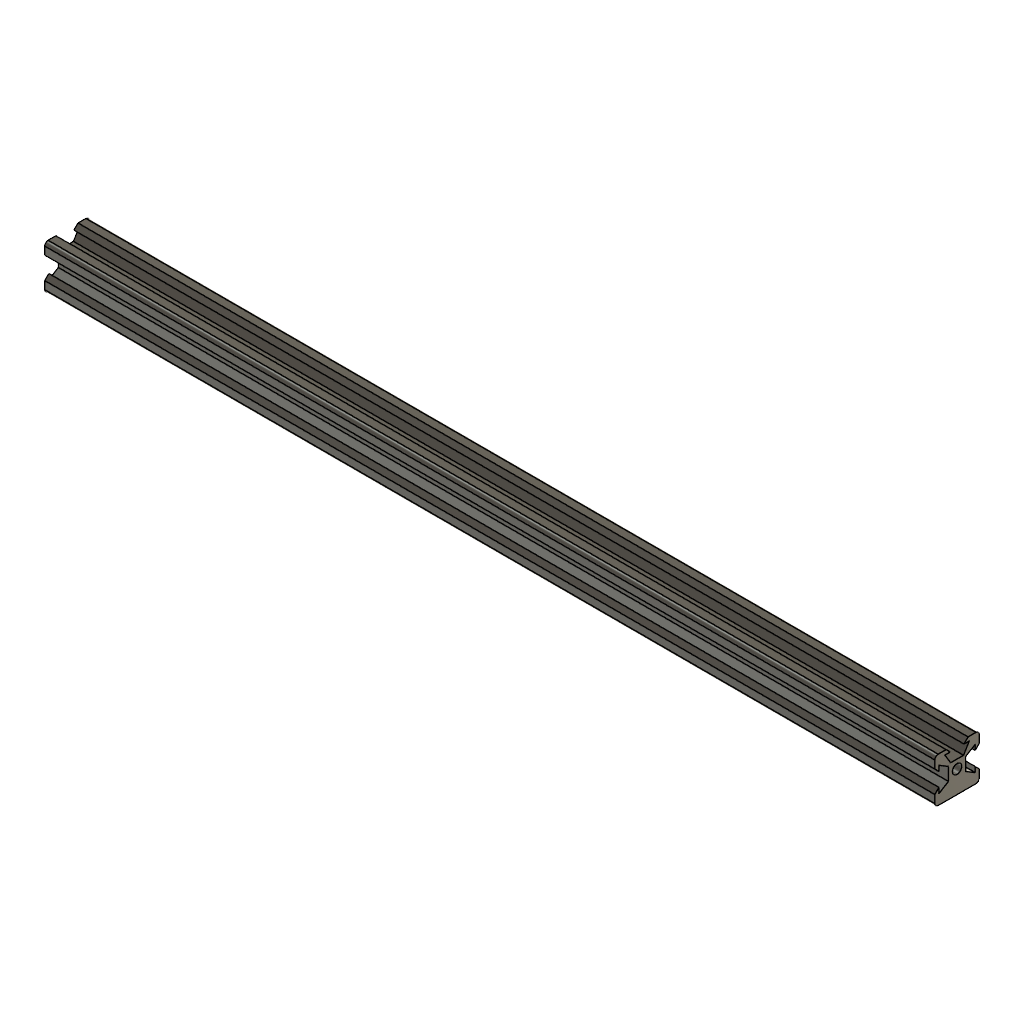
Plotter (Autodesk Fusion 360 archive; units mm, degrees)
design "2020 Extrusion 400mm"
part number: 2026-11-06-18-32-31-215
Autodesk Fusion 360 part; units mm, degrees
sketch "Sketch1" plane through (0, 0, 0) normal (1, 0, 0) x (0, 1, 0)
  line L0 (1.5, 0) -> (18.5, 0)
  line L1 (20, 1.5) -> (20, 18.5)
  line L2 (18.5, 20) -> (1.5, 20)
  line L3 (0, 18.5) -> (0, 1.5)
  line L4 (0, 10) -> (20, 10) construction
  line L5 (10, 20) -> (10, 0) construction
  circle A0 centre (10, 10) radius 2.1
  line L6 (18.15, 1.85) -> (1.85, 1.85)
  line L7 (1.85, 1.85) -> (1.85, 18.15)
  line L8 (1.85, 18.15) -> (18.15, 18.15)
  line L9 (18.15, 18.15) -> (18.15, 1.85)
  line L10 (18.15, 1.85) -> (1.85, 18.15) construction
  line L11 (1.85, 1.85) -> (18.15, 18.15) construction
  line L12 (6.9, 1.85) -> (13.1, 1.85)
  line L13 (13.1, 1.85) -> (13.1, 0)
  line L14 (13.1, 0) -> (6.9, 0)
  line L15 (6.9, 0) -> (6.9, 1.85)
  line L16 (6.9, 1.2297) -> (10, 1.2297) construction
  line L17 (10, 0.7) -> (13.1, 0.7) construction
  line L18 (13.1, 1.85) -> (14.95, 0)
  line L19 (13.1, 1.85) -> (15.7163, 1.85) construction
  line L20 (6.9, 1.85) -> (5.05, 0)
  line L21 (6.9, 1.85) -> (9.5163, 1.85) construction
  line L22 (4.5, 1.85) -> (15.5, 1.85)
  line L23 (15.5, 1.85) -> (15.5, 6.1238)
  line L24 (15.5, 6.1238) -> (4.5, 6.1238)
  line L25 (4.5, 6.1238) -> (4.5, 1.85)
  line L26 (4.5, 4.5637) -> (10, 4.5637) construction
  line L27 (10, 3.5) -> (15.5, 3.5) construction
  arc A1 (1.5, 20) -> (0, 18.5) centre (1.5, 18.5) ccw
  arc A2 (20, 18.5) -> (18.5, 20) centre (18.5, 18.5) ccw
  arc A3 (18.5, 0) -> (20, 1.5) centre (18.5, 1.5) ccw
  arc A4 (0, 1.5) -> (1.5, 0) centre (1.5, 1.5) ccw
  line L28 (4.5, 1.85) -> (7.0952, 6.1238)
  line L29 (15.5, 1.85) -> (12.9048, 6.1238)
  point P0 (20, 0)
  point P1 (0, 20)
  point P2 (10, 10)
  dimension "d1" = 20
  dimension "d2" = 20
  dimension "d3" = 4.2
  dimension "d4" = 16.3
  dimension "d5" = 6.2
  dimension "d6" = 45
  dimension "d7" = 135
  dimension "d9" = 6.1238
  dimension "d10" = 11
  dimension "d11" = 1.5
  dimension "d12" = 5
  dimension "d13" = 5
  constraint horizontal L0
  constraint vertical L1
  constraint horizontal L2
  constraint vertical L3
  constraint midpoint L4 P2
  constraint horizontal L6
  constraint perpendicular L6 L7
  constraint parallel L6 L8
  constraint parallel L7 L9
  constraint coincident L10 P2
  constraint coincident L11 P2
  constraint coincident P2 A0.centre
  constraint equal L7 L8
  constraint horizontal L12
  constraint vertical L13
  constraint horizontal L14
  constraint vertical L15
  constraint coincident L0 L13.end
  constraint coincident L6 L12.start
  constraint coincident L15 L16.start
  constraint coincident L5 L16.end
  constraint perpendicular L5 L16
  constraint coincident L5 L17.start
  constraint coincident L13 L17.end
  constraint perpendicular L13 L17
  constraint equal L16 L17
  constraint horizontal L19
  constraint coincident L0 L18.end
  constraint horizontal L21
  constraint coincident L0 L20.end
  constraint horizontal L22
  constraint vertical L23
  constraint horizontal L24
  constraint vertical L25
  constraint coincident L6 L22.start
  constraint coincident L25 L26.start
  constraint perpendicular L25 L26
  constraint coincident L5 L27.start
  constraint coincident L23 L27.end
  constraint perpendicular L23 L27
  constraint equal L26 L27
  constraint coincident L5 L26.end
  constraint coincident L2 L5.start
  constraint coincident L3 L4.start
  constraint coincident P1 L2
  constraint coincident P1 L3
  constraint tangent L2 A1
  constraint tangent L3 A1
  constraint coincident L1 L4.end
  constraint tangent L1 A2
  constraint tangent L2 A2
  constraint equal A1 A2
  constraint coincident L0 L5.end
  constraint coincident P0 L0
  constraint coincident P0 L1
  constraint tangent L0 A3
  constraint tangent L1 A3
  constraint equal A1 A3
  constraint coincident origin L0
  constraint coincident origin L3
  constraint tangent L0 A4
  constraint tangent L3 A4
  constraint equal A1 A4
  constraint coincident L24 L28.end
  constraint coincident L24 L29.end
  measures "d1" distance of origin P0
  measures "d2" distance of origin P1
  measures "d3" diameter of A0
  measures "d4" distance of L6.end L7.end
  measures "d5" distance of L13 L15
  measures "d6" angle of L18 L19
  measures "d7" angle of L20 L21
  measures "d9" distance of L0 L24
  measures "d10" distance of L23.end L24.end
  measures "d11" radius of A1
  measures "d12" distance of L22.start L28.end
  measures "d13" distance of L22.end L29.end
extrude "Extrude1" add sketch "Sketch1" along normal blind 400
extrude "Extrude2" cut sketch "Sketch1" along normal blind 400 contours L0 L15 L20 | L0 L6 L12 L13 L14 L15 L22 | L6 L12 L22 L24 L28 L29 | L0 L13 L18
move_body "Move1" bodies 1 to x (1, 0, 0) y (0, -1, 0) z (0, 0, -1) at (0, 20, 20)
pattern_circular "C-Pattern1" count 4 over 360 about axis through (0, 10, 10) along (1, 0, 0) of "Extrude2"
equation "d4 = 20 mm - ( ( 2 * 1.85 ) * 1 mm )"
